Charger (Autodesk Fusion 360 design; units mm, degrees)
Autodesk Fusion 360 part; units mm, degrees
sketch "Sketch1" plane through (0, 0, 0) normal (0, 1, 0) x (1, 0, 0)
  line L0 (35, -13.5) -> (-35, -13.5)
  line L1 (-35, -13.5) -> (-35, 13.5)
  line L2 (-35, 13.5) -> (35, 13.5)
  line L3 (35, 13.5) -> (35, -13.5)
  line L4 (36.5, -15) -> (-36.5, -15)
  line L5 (-36.5, -15) -> (-36.5, 15)
  line L6 (-36.5, 15) -> (36.5, 15)
  line L7 (36.5, 15) -> (36.5, -15)
  line L8 (0, 15) -> (0, 3)
  line L9 (-36.5, 0) -> (-8.4, 0)
  line L10 (36.5, 0) -> (8.4, 0)
  line L11 (0, -15) -> (0, -5.9)
  line L12 (-8.4, -5.9) -> (8.4, -5.9)
  line L13 (8.4, -5.9) -> (8.4, 3)
  line L14 (8.4, 3) -> (-8.4, 3)
  line L15 (-8.4, 3) -> (-8.4, -5.9)
  dimension "d1" = 70
  dimension "d2" = 27
  dimension "d3" = 73
  dimension "d4" = 30
  dimension "d5" = 12
  dimension "d6" = 28.1
  dimension "d7" = 28.1
  dimension "d8" = 9.1
  constraint perpendicular L0 L1
  constraint parallel L0 L2
  constraint parallel L1 L3
  constraint horizontal L0
  constraint perpendicular L4 L5
  constraint parallel L4 L6
  constraint parallel L5 L7
  constraint horizontal L4
  constraint midpoint L6 L8.start
  constraint vertical L8
  constraint midpoint L5 L9.start
  constraint horizontal L9
  constraint midpoint L7 L10.start
  constraint horizontal L10
  constraint midpoint L4 L11.start
  constraint vertical L11
  constraint horizontal L12
  constraint vertical L13
  constraint horizontal L14
  constraint vertical L15
  measures "d1" distance of L1.end L2.end
  measures "d2" distance of L0.end L1.end
  measures "d3" distance of L5.end L6.end
  measures "d4" distance of L4.end L5.end
  measures "d5" distance of L8.start L8.end
  measures "d6" distance of L9.start L9.end
  measures "d7" distance of L10.start L10.end
  measures "d8" distance of L11.start L11.end
extrude "Extrude1" add sketch "Sketch1" along normal blind 1.5 contours L0 L3 L4 L7 L10 L11 | L0 L3 L10 L11 L12 L13 | L0 L1 L4 L5 L9 L11 | L0 L1 L9 L11 L12 L15 | L2 L3 L8 L10 L13 L14 | L2 L3 L6 L7 L8 L10 | L1 L2 L5 L6 L8 L9 | L1 L2 L8 L9 L14 L15
sketch "Sketch2" plane through (0, 1.5, 0) normal (0, 1, 0) x (-1, 0, 0)
  line L0 (8.4, 5.9) -> (8.4, -3)
  line L1 (8.4, -3) -> (-8.4, -3)
  line L2 (-8.4, -3) -> (-8.4, 5.9)
  line L3 (-8.4, 5.9) -> (8.4, 5.9)
  line L4 (-36.5, -15) -> (36.5, -15)
  line L5 (36.5, -15) -> (36.5, 15)
  line L6 (36.5, 15) -> (-36.5, 15)
  line L7 (-36.5, 15) -> (-36.5, -15)
  line L8 (-35, 13.5) -> (35, 13.5)
  line L9 (35, 13.5) -> (35, -13.5)
  line L10 (35, -13.5) -> (-35, -13.5)
  line L11 (-35, -13.5) -> (-35, 13.5)
  point P0 (-35, 13.5)
  constraint perpendicular L8 L9
  constraint parallel L8 L10
  constraint parallel L9 L11
  constraint horizontal L8
  constraint coincident P0 L8.start
extrude "Extrude2" add sketch "Sketch2" along normal blind 98.75 contours L4 L5 L6 L7
sketch "Sketch3" plane through (0, 0, -15) normal (0, 0, -1) x (-1, 0, 0)
  line L0 (-36.5, 0) -> (36.5, 0)
  line L1 (36.5, 0) -> (36.5, 100.25)
  line L2 (36.5, 100.25) -> (-36.5, 100.25)
  line L3 (-36.5, 100.25) -> (-36.5, 0)
  line L4 (0, 0) -> (-1.5, 0)
  line L5 (0, 0) -> (1.5, 0)
  line L6 (-1.5, 0) -> (1.5, 0)
  line L7 (1.5, 0) -> (1.5, 65)
  line L8 (1.5, 65) -> (-1.5, 65)
  line L9 (-1.5, 65) -> (-1.5, 0)
  dimension "d13" = 1.5
  dimension "d14" = 1.5
  dimension "d15" = 3
  dimension "d16" = 65
  constraint coincident L4.start L5.start
  constraint horizontal L4
  constraint horizontal L5
  constraint horizontal L6
  constraint vertical L7
  constraint horizontal L8
  constraint vertical L9
  measures "d13" distance of L4.start L4.end
  measures "d14" distance of L4.start L5.end
  measures "d15" distance of L4.end L5.end
  measures "d16" distance of L4.end L8.end
extrude "Extrude3" add sketch "Sketch3" along normal blind 45 contours L0 L4 L5 L6 L7 L8 L9
sketch "Sketch4" plane through (-1.5, 0, 0) normal (-1, 0, 0) x (0, 0, 1)
  line L0 (-15, 0) -> (-15, 65)
  line L1 (-15, 65) -> (-60, 65)
  line L2 (-60, 65) -> (-60, 0)
  line L3 (-60, 0) -> (-15, 0)
  line L4 (-60, 65) -> (-26, 0)
  constraint coincident L1.end L2.start
  constraint coincident L3 L4.end
extrude "Extrude4" cut sketch "Sketch4" against normal up to surface (3 mm away) contours L2 L3 L4
sketch "Sketch6" plane through (0, 0, 0) normal (0, -1, 0) x (1, 0, 0)
  line L0 (1.5, -26) -> (1.5, -15)
  line L1 (1.5, -15) -> (36.5, -15)
  line L2 (36.5, -15) -> (36.5, 15)
  line L3 (36.5, 15) -> (-36.5, 15)
  line L4 (-36.5, 15) -> (-36.5, -15)
  line L5 (-36.5, -15) -> (-1.5, -15)
  line L6 (-1.5, -15) -> (-1.5, -26)
  line L7 (-8.4, -3) -> (-8.4, 5.9)
  line L8 (-8.4, 5.9) -> (8.4, 5.9)
  line L9 (8.4, 5.9) -> (8.4, -3)
  line L10 (8.4, -3) -> (-8.4, -3)
  line L11 (-54, 28) -> (60, 28)
  line L12 (60, 28) -> (60, -72)
  line L13 (60, -72) -> (-54, -72)
  line L14 (-54, -72) -> (-54, 28)
  line L15 (-1.5, -26) -> (1.5, -26)
  constraint horizontal L11
  constraint vertical L12
  constraint horizontal L13
  constraint vertical L14
extrude "Extrude6" cut sketch "Sketch6" along normal blind 10 contours L0 L1 L2 L3 L4 L5 L6 L15 | L7 L8 L9 L10 | L11 L12 L13 L14
sketch "Sketch8" plane through (0, -10.6783, -20.4144) normal (0, -0.463498, -0.886098) x (-1, 0, 0)
  line L0 (-1.5, 85.4062) -> (-1.5, 12.0509)
  line L1 (-1.5, 12.0509) -> (1.5, 12.0509)
  line L2 (1.5, 12.0509) -> (1.5, 85.4062)
  line L3 (1.5, 85.4062) -> (-1.5, 85.4062)
  line L4 (1.5, 12.0509) -> (13.5, 12.0509)
  line L5 (-1.5, 12.0509) -> (-13.5, 12.0509)
  line L6 (-1.5, 85.4062) -> (-13.5, 85.4062)
  line L7 (1.5, 85.4062) -> (13.5, 85.4062)
  line L8 (-13.5, 12.0509) -> (13.5, 12.0509)
  line L9 (13.5, 12.0509) -> (13.5, 85.4062)
  line L10 (13.5, 85.4062) -> (-13.5, 85.4062)
  line L11 (-13.5, 85.4062) -> (-13.5, 12.0509)
  dimension "d36" = 12
  dimension "d37" = 12
  dimension "d38" = 12
  dimension "d39" = 12
  constraint coincident L1.end L2.start
  constraint horizontal L4
  constraint coincident L0.end L1.start
  constraint horizontal L5
  constraint coincident L0.start L3.end
  constraint horizontal L6
  constraint coincident L2.end L3.start
  constraint horizontal L7
  constraint horizontal L8
  constraint vertical L9
  constraint horizontal L10
  constraint vertical L11
  measures "d36" distance of L1.end L4.end
  measures "d37" distance of L0.end L5.end
  measures "d38" distance of L0.start L6.end
  measures "d39" distance of L2.end L7.end
extrude "Extrude8" add sketch "Sketch8" along normal blind 2
sketch "Sketch9" plane through (0, 0, 0) normal (0, -1, 0) x (1, 0, 0)
  line L0 (-1.5, -26) -> (1.5, -26)
  line L1 (1.5, -26) -> (1.5, -15)
  line L2 (1.5, -15) -> (36.5, -15)
  line L3 (36.5, -15) -> (36.5, 15)
  line L4 (36.5, 15) -> (-36.5, 15)
  line L5 (-36.5, 15) -> (-36.5, -15)
  line L6 (-36.5, -15) -> (-1.5, -15)
  line L7 (-1.5, -15) -> (-1.5, -26)
  line L8 (-8.4, -3) -> (-8.4, 5.9)
  line L9 (-8.4, 5.9) -> (8.4, 5.9)
  line L10 (8.4, 5.9) -> (8.4, -3)
  line L11 (8.4, -3) -> (-8.4, -3)
  line L12 (-54, -56) -> (54, -56)
  line L13 (54, -56) -> (54, 48)
  line L14 (54, 48) -> (-54, 48)
  line L15 (-54, 48) -> (-54, -56)
  constraint horizontal L12
  constraint vertical L13
  constraint horizontal L14
  constraint vertical L15
extrude "Extrude9" cut sketch "Sketch9" along normal blind 15 contours L0 L1 L2 L3 L4 L5 L6 L7 | L8 L9 L10 L11 | L12 L13 L14 L15
fillet "Fillet1" radius 4 8 edges at (35, 50.875, 13.5) (-35, 50.875, 13.5) (-36.5, 50.125, 15) (36.5, 50.125, 15) (36.5, 50.125, -15) (35, 50.875, -13.5) (-36.5, 50.125, -15) (-35, 50.875, -13.5)
